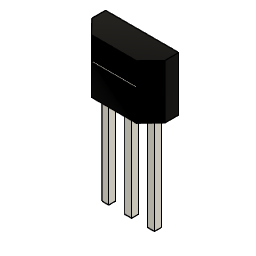
Attitude Indicator v47 (Autodesk Fusion 360 archive; units mm, degrees)
design "Hall Effect Sensor SS494B"
Autodesk Fusion 360 part; units mm, degrees
sketch "Top Profile" plane through (0, 0, 0) normal (0, 0, 1) x (1, 0, 0)
  line L0 (2.03, -0.785) -> (-2.03, -0.785)
  line L1 (-2.03, -0.785) -> (-2.03, 0.785)
  line L2 (-2.03, 0.785) -> (2.03, 0.785)
  line L3 (2.03, 0.785) -> (2.03, -0.785)
  line L4 (2.03, -0.785) -> (-2.03, 0.785) construction
  line L5 (-2.03, -0.785) -> (2.03, 0.785) construction
  line L6 (-1.25, -0.785) -> (-2.03, 0.025)
  line L7 (0, 0) -> (0, 0.785) construction
  line L8 (1.25, -0.785) -> (2.03, 0.025)
  line L9 (-1.08, 0.01) -> (-1.46, 0.01)
  line L10 (-1.46, 0.01) -> (-1.46, 0.39)
  line L11 (-1.46, 0.39) -> (-1.08, 0.39)
  line L12 (-1.08, 0.39) -> (-1.08, 0.01)
  line L13 (-1.08, 0.01) -> (-1.46, 0.39) construction
  line L14 (-1.46, 0.01) -> (-1.08, 0.39) construction
  line L15 (0.19, 0.01) -> (-0.19, 0.01)
  line L16 (-0.19, 0.01) -> (-0.19, 0.39)
  line L17 (-0.19, 0.39) -> (0.19, 0.39)
  line L18 (0.19, 0.39) -> (0.19, 0.01)
  line L19 (0.19, 0.01) -> (-0.19, 0.39) construction
  line L20 (-0.19, 0.01) -> (0.19, 0.39) construction
  line L21 (1.08, 0.01) -> (1.46, 0.01)
  line L22 (1.46, 0.01) -> (1.46, 0.39)
  line L23 (1.46, 0.39) -> (1.08, 0.39)
  line L24 (1.08, 0.39) -> (1.08, 0.01)
  point P0 (-1.27, 0.2)
  point P1 (0, 0.2)
  dimension "d1" = 4.06
  dimension "d2" = 1.57
  dimension "d3" = 0.76
  dimension "d4" = 1.25
  dimension "d5" = 0.38
  dimension "d6" = 1.27
  dimension "d7" = 0.2
  dimension "d8" = 0.38
  constraint horizontal L0
  constraint perpendicular L0 L1
  constraint parallel L0 L2
  constraint parallel L1 L3
  constraint coincident L4 L7.start
  constraint coincident L5 L7.start
  constraint coincident L7.start origin
  constraint coincident L0 L6.start
  constraint coincident L1 L6.end
  constraint midpoint L2 L7.end
  constraint symmetric L6.start L7 L8.start
  constraint symmetric L6.end L7 L8.end
  constraint horizontal L9
  constraint perpendicular L9 L10
  constraint parallel L9 L11
  constraint parallel L10 L12
  constraint coincident L13 P0
  constraint coincident L14 P0
  constraint horizontal L15
  constraint perpendicular L15 L16
  constraint parallel L15 L17
  constraint parallel L16 L18
  constraint coincident L19 P1
  constraint coincident L20 P1
  constraint vertical L7.start P1
  constraint horizontal P0 P1
  constraint equal L11 L17
  constraint equal L12 L16
  constraint symmetric L7 L9.start L21.start
  constraint symmetric L7 L9.end L21.end
  constraint symmetric L7 L10.end L22.end
  constraint symmetric L7 L11.end L23.end
  measures "d1" distance of L1.end L2.end
  measures "d2" distance of L0.end L1.end
  measures "d3" distance of L2 L6.end
  measures "d4" horizontal distance of L7.start L6.start
  measures "d5" distance of L10.end L11.end
  measures "d6" distance of P0 P1
  measures "d7" distance of L7.start P1
  measures "d8" distance of L9.start L11.end
extrude "Extrude1" add sketch "Top Profile" along normal blind 3 contours L0 L1 L2 L3 L6 L8 | L9 L10 L11 L12 | L15 L16 L17 L18 | L21 L22 L23 L24
extrude "Extrude2" add sketch "Top Profile" against normal blind 5.5 contours L9 L10 L11 L12 | L15 L16 L17 L18 | L21 L22 L23 L24
sketch "Mag Slot (South should face this way)" plane through (0, -0.785, 0) normal (0, -1, 0) x (1, 0, 0)
  line L0 (-1.25, 0) -> (1.25, 0)
  line L1 (1.25, 0) -> (1.25, 3)
  line L2 (1.25, 3) -> (-1.25, 3)
  line L3 (-1.25, 3) -> (-1.25, 0)
  line L4 (1.25, 1.69) -> (-1.25, 1.69)
  line L5 (-1.25, 1.69) -> (-1.25, 1.79)
  line L6 (-1.25, 1.79) -> (1.25, 1.79)
  line L7 (1.25, 1.79) -> (1.25, 1.69)
  line L8 (1.25, 1.69) -> (-1.25, 1.79) construction
  line L9 (-1.25, 1.69) -> (1.25, 1.79) construction
  point P0 (0, 1.74)
  dimension "d13" = 0.1
  dimension "d14" = 1.74
  constraint horizontal L4
  constraint perpendicular L4 L5
  constraint parallel L4 L6
  constraint parallel L5 L7
  constraint coincident L8 P0
  constraint coincident L9 P0
  constraint vertical P0 origin
  constraint coincident L1 L6.end
  measures "d13" distance of L4.start L6.end
  measures "d14" distance of P0 origin
extrude "Extrude3" cut sketch "Mag Slot (South should face this way)" against normal blind 0.1 contours L1 L3 L4 L5 L6 L7
equation "d4 = ( 2.5 / 2 ) * 1 mm"
equation "d11 = -15.5 mm + 10 mm"
